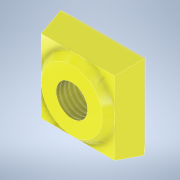
# Autodesk Inventor part: 24-10-25-sliding-brass-Lawrence-A2213271-v1
Saved by Autodesk Inventor 2022 (Build 260153000, 153)
## iProperties
Created: 2024-10-25
Part Number: 24-10-25-sliding-brass-Lawrence-A2213271-v1
Material: Generic
Document SubType Name: Modeling
Designer: Dell
Density: 1 g/cm^3
Appearance: Yellow
Author: Dell
Autodesk Inventor part; units mm, degrees
ref_plane "YZ Plane" through (0, 0, 0) normal (1, 0, 0) x (0, 1, 0)
ref_plane "XZ Plane" through (0, 0, 0) normal (0, 1, 0) x (-1, 0, 0)
ref_plane "XY Plane" through (0, 0, 0) normal (0, 0, 1) x (1, 0, 0)
sketch "Sketch1" plane through (0, 0, 0) normal (0, 0, 1) x (1, 0, 0)
  line L0 (-14.21, 14.21) -> (14.21, 14.21)
  line L1 (14.21, 14.21) -> (14.21, -14.21)
  line L2 (14.21, -14.21) -> (-14.21, -14.21)
  line L3 (-14.21, -14.21) -> (-14.21, 14.21)
  line L4 (-14.21, 14.21) -> (14.21, -14.21) construction
  line L5 (14.21, 14.21) -> (-14.21, -14.21) construction
  point P0 (0, 0)
  dimension "d0" = 28.42
  dimension "d1" = 28.42
  constraints: 12 end point, 2 midpoint, 2 parallel, 1 horizontal, 1 perpendicular
  measures "d0" distance of L1.end L2.end
  measures "d1" distance of L0.end L1.end
extrude "Extrusion1" add sketch "Sketch1" along normal blind 10 draft -12
sketch "Sketch2" plane through (0, 0, 10) normal (0, 0, 1) x (1, 0, 0)
  circle A0 centre (0, 0) radius 12.0844
  line L0 (-12.0844, 12.0844) -> (12.0844, 12.0844) projected
  constraints: 1 centre point, 1 coincident, 1 tangent
extrude "Extrusion2" add sketch "Sketch2" along normal blind 2
chamfer "Chamfer1" distance 2 angle 45 1 edges at (-12.0844, 0, 12)
sketch "Sketch3" plane through (0, 0, 12) normal (0, 0, 1) x (1, 0, 0)
  circle A0 centre (0, 0) radius 5.19
  dimension "d9" = 10.38
  constraints: 1 centre point, 1 coincident
  measures "d9" diameter of A0
extrude "Extrusion3" cut sketch "Sketch3" against normal blind 8
sketch "Sketch4" plane through (0, 0, 0) normal (0, 0, -1) x (-1, 0, 0)
  point P0 (0, 0)
chamfer "Chamfer2" distance 2 angle 45 4 edges at (-14.21, 0, 0) (0, 14.21, 0) (14.21, 0, 0) (0, -14.21, 0)
thread "Thread1" size "M12x1.5" class "6H" standard "ISO Metric profile" length 8
body "Solid1"
